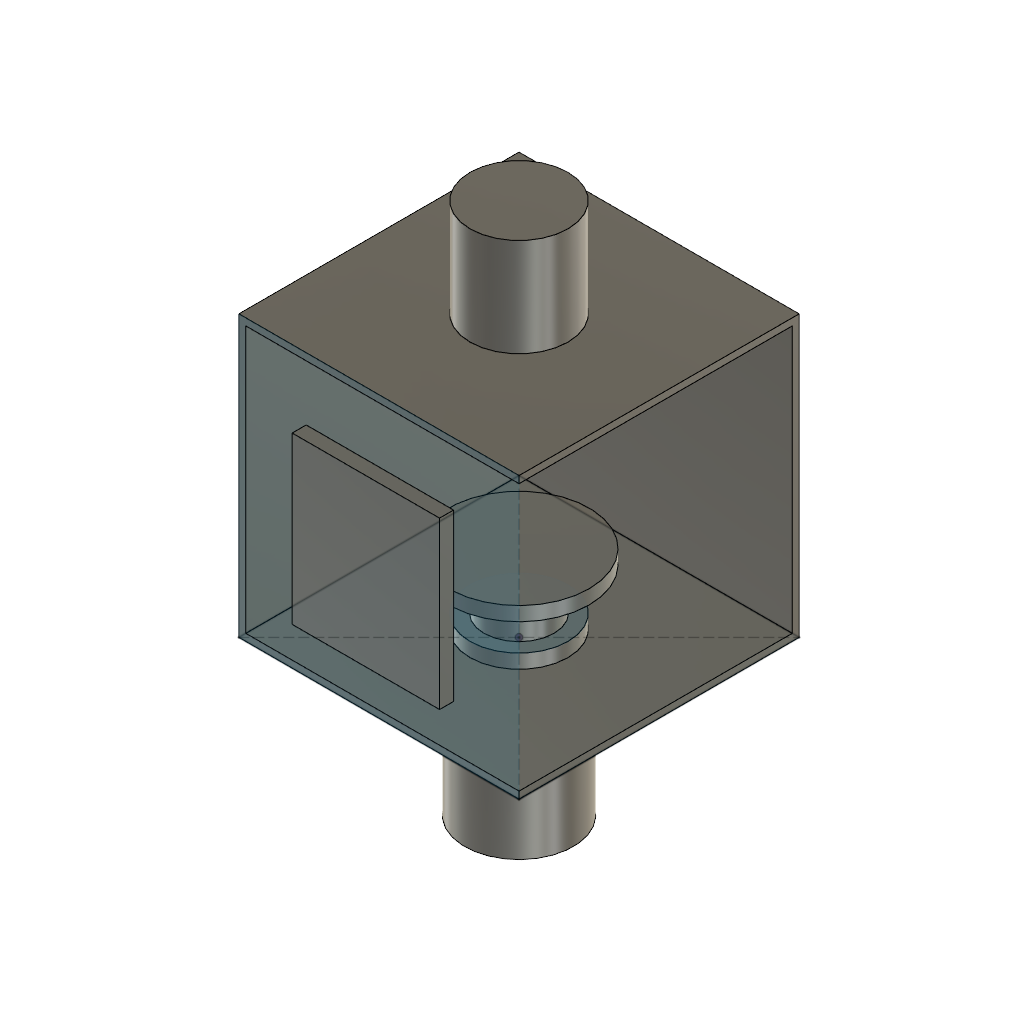
Vacuum Chamber Concept (Autodesk Fusion 360 design; units mm, degrees)
part number: 2026-11-04-12-01-44-136
Autodesk Fusion 360 part; units mm, degrees
sketch "Sketch1" plane through (0, 0, 0) normal (0, 0, 1) x (1, 0, 0)
  line L0 (100, -100) -> (-100, -100)
  line L1 (-100, -100) -> (-100, 100)
  line L2 (-100, 100) -> (100, 100)
  line L3 (100, 100) -> (100, -100)
  line L4 (100, -100) -> (-100, 100) construction
  line L5 (-100, -100) -> (100, 100) construction
  dimension "d3" = 200
  dimension "d4" = 200
  constraint horizontal L0
  constraint perpendicular L0 L1
  constraint parallel L0 L2
  constraint parallel L1 L3
  constraint coincident L4 origin
  constraint coincident L5 origin
  measures "d3" distance of L0.end L1.end
  measures "d4" distance of L0.start L0.end
extrude "Extrude2" add sketch "Sketch1" along normal blind 200 makes body 1
sketch "Sketch2" plane through (0, -100, 0) normal (0, -1, 0) x (1, 0, 0)
  line L0 (-100, 0) -> (100, 0)
  line L1 (100, 0) -> (100, 200)
  line L2 (100, 200) -> (-100, 200)
  line L3 (-100, 200) -> (-100, 0)
shell "Shell1" thickness 5 removed faces 2 at (100, 33.3333, 66.6667) at (33.3333, -100, 66.6667) on bodies 1
sketch "Sketch3" plane through (0, 0, 5) normal (0, 0, 1) x (-1, 0, 0)
  line L0 (-100, -95) -> (95, -95)
  line L1 (95, -95) -> (95, 100)
  line L2 (95, 100) -> (-100, 100)
  line L3 (-100, 100) -> (-100, -95)
  circle A0 centre (0, 0) radius 35
  dimension "d8" = 70
  constraint coincident A0.centre origin
  measures "d8" diameter of A0
extrude "Extrude3" add sketch "Sketch3" along normal blind 10 contours A0 bodies 1
sketch "Sketch4" plane through (0, 0, 15) normal (0, 0, 1) x (-1, 0, 0)
  circle A0 centre (0, 0) radius 35
sketch "Sketch5" plane through (0, 0, 15) normal (0, 0, 1) x (-1, 0, 0)
  circle A0 centre (0, 0) radius 25
  dimension "d11" = 50
  constraint coincident A0.centre origin
  measures "d11" diameter of A0
extrude "Extrude4" add sketch "Sketch5" along normal blind 30 bodies 1
sketch "Sketch6" plane through (0, 0, 45) normal (0, 0, 1) x (-1, 0, 0)
  circle A0 centre (0, 0) radius 25
  circle A1 centre (0, 0) radius 50
  dimension "d14" = 100
  constraint coincident A0.centre A1.centre
  measures "d14" diameter of A1
extrude "Extrude5" add sketch "Sketch6" along normal blind 10 contours A0 | A1 bodies 1
sketch "Sketch7" plane through (0, 0, 200) normal (0, 0, 1) x (-1, 0, 0)
  line L0 (-100, -100) -> (100, -100)
  line L1 (100, -100) -> (100, 100)
  line L2 (100, 100) -> (-100, 100)
  line L3 (-100, 100) -> (-100, -100)
  circle A0 centre (0, 0) radius 35
  dimension "d17" = 70
  constraint coincident A0.centre origin
  measures "d17" diameter of A0
extrude "Extrude6" add sketch "Sketch7" along normal blind 70 contours A0 bodies 1
sketch "Sketch8" plane through (0, 0, 0) normal (0, 0, 1) x (1, 0, 0)
  circle A0 centre (0, 0) radius 58.5992
  constraint coincident A0.centre origin
extrude "Extrude7" add sketch "Sketch8" against normal blind 15 bodies 1
sketch "Sketch9" plane through (0, 0, -15) normal (0, 0, -1) x (1, 0, 0)
  circle A0 centre (0, 0) radius 58.5992
  circle A1 centre (0, 0) radius 38.7684
  constraint coincident A0.centre A1.centre
extrude "Extrude8" add sketch "Sketch9" along normal blind 95 contours A1 bodies 1
sketch "Sketch10" plane through (0, 0, -110) normal (0, 0, -1) x (1, 0, 0)
  circle A0 centre (0, 0) radius 38.7684
  circle A1 centre (0, 0) radius 29.0976
  constraint coincident A0.centre A1.centre
extrude "Extrude9" cut sketch "Sketch10" against normal blind 100 contours A1 bodies 1
sketch "Sketch11" plane through (0, -100, 0) normal (0, -1, 0) x (1, 0, 0)
  line L0 (-51.8997, 155.3523) -> (53.3012, 155.3523)
  line L1 (53.3012, 155.3523) -> (53.3012, 37.0668)
  line L2 (53.3012, 37.0668) -> (-51.8997, 37.0668)
  line L3 (-51.8997, 37.0668) -> (-51.8997, 155.3523)
  constraint horizontal L0
  constraint vertical L1
  constraint horizontal L2
  constraint vertical L3
extrude "Extrude10" add sketch "Sketch11" along normal blind 10 separate body makes body 2
